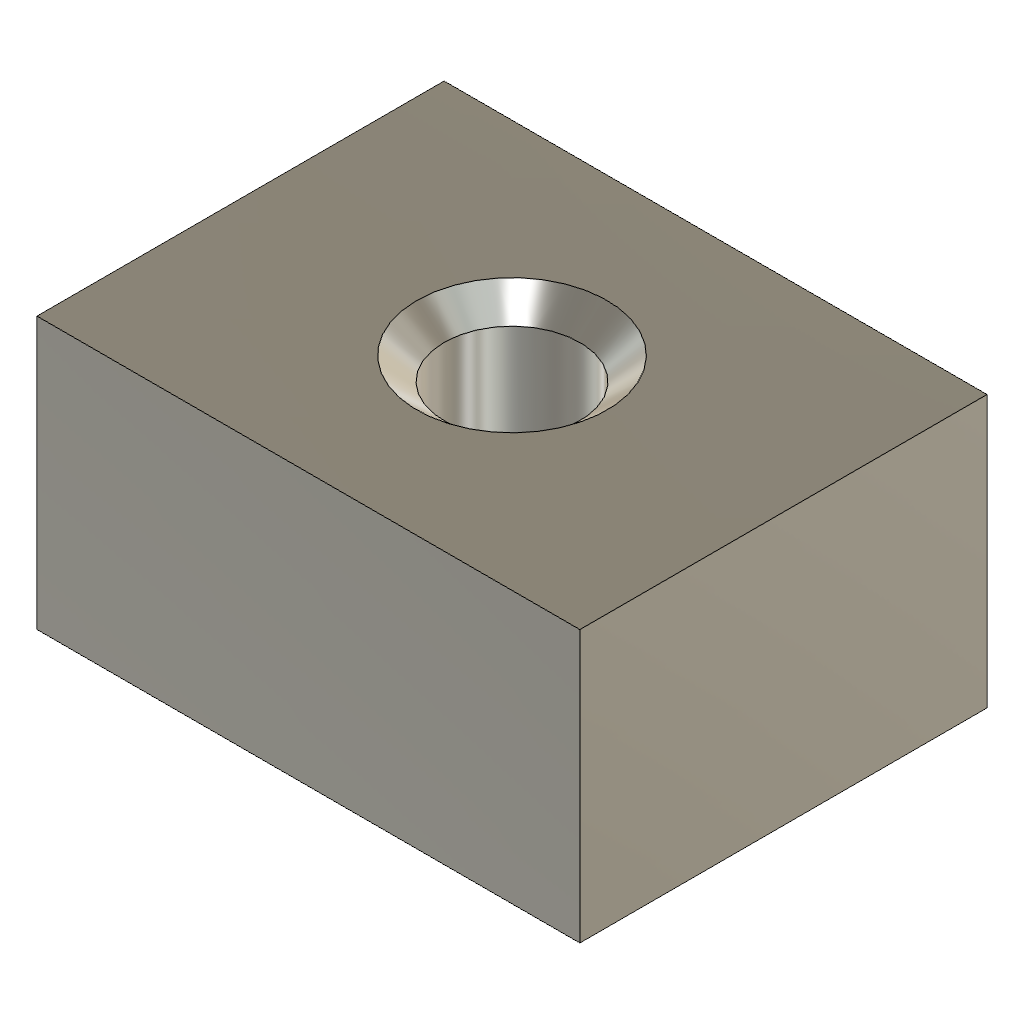
vendor_BevelBoreAngle (Autodesk Fusion 360 design; units mm, degrees)
Autodesk Fusion 360 part; units mm, degrees
sketch "Base sketch" plane through (0, 0, 0) normal (0, 0, 1) x (1, 0, 0)
  line L0 (0, 0) -> (40, 0)
  line L1 (40, 0) -> (40, 30)
  line L2 (40, 30) -> (0, 30)
  line L3 (0, 30) -> (0, 0)
extrude "Base extrude" add sketch "Base sketch" along normal blind 20
sketch "Bore sketch" plane through (0, 0, 0) normal (0, 0, 1) x (1, 0, 0)
  circle A0 centre (20, 15) radius 5
extrude "Bore" cut sketch "Bore sketch" along normal blind 20
chamfer "Bore bevel" distance 2 angle 40 1 edges at (15.3384, 16.8081, 20) measured on face at (5, 15, 20) tangent chain off
equation "height = 20.0 mm"
